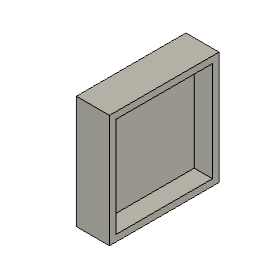
Ensamble_1 (Autodesk Fusion 360 archive; units mm, degrees)
design "caja_pantalla"
Autodesk Fusion 360 part; units mm, degrees
(part 1 of 2)
sketch "Boceto2" plane through (0, 0, 0) normal (1, 0, 0) x (0, 0, -1)
  line L0 (16.5, 17) -> (-16.5, 17)
  line L1 (-16.5, 17) -> (-16.5, -17)
  line L2 (-16.5, -17) -> (16.5, -17)
  line L3 (16.5, -17) -> (16.5, 17)
  line L4 (16.5, 17) -> (-16.5, -17) construction
  line L5 (-16.5, 17) -> (16.5, -17) construction
  dimension "d1" = 33
  dimension "d2" = 34
  constraint horizontal L0
  constraint perpendicular L0 L1
  constraint parallel L0 L2
  constraint parallel L1 L3
  constraint coincident L4 origin
  constraint coincident L5 origin
  measures "d1" distance of L1.end L2.end
  measures "d2" distance of L0.end L1.end
extrude "Extruir1" add sketch "Boceto2" along normal blind 10
sketch "Boceto3" plane through (10, 0, 0) normal (1, 0, 0) x (0, 0, -1)
  line L0 (16.5, -17) -> (16.5, 17)
  line L1 (16.5, 17) -> (-16.5, 17)
  line L2 (-16.5, 17) -> (-16.5, -17)
  line L3 (-16.5, -17) -> (16.5, -17)
  line L4 (14.5, 15) -> (-14.5, 15)
  line L5 (-14.5, 15) -> (-14.5, -15)
  line L6 (-14.5, -15) -> (14.5, -15)
  line L7 (14.5, -15) -> (14.5, 15)
  line L8 (14.5, 15) -> (-14.5, -15) construction
  line L9 (-14.5, 15) -> (14.5, -15) construction
  dimension "d5" = 29
  dimension "d6" = 30
  constraint horizontal L4
  constraint perpendicular L4 L5
  constraint parallel L4 L6
  constraint parallel L5 L7
  constraint coincident L8 origin
  constraint coincident L9 origin
  measures "d5" distance of L5.end L6.end
  measures "d6" distance of L4.end L5.end
extrude "Extruir2" cut sketch "Boceto3" against normal blind 5.5 contours L4 L5 L6 L7
sketch "Boceto4" plane through (4.5, 0, 0) normal (1, 0, 0) x (0, 0, -1)
  line L0 (14.5, -15) -> (14.5, 15)
  line L1 (14.5, 15) -> (-14.5, 15)
  line L2 (-14.5, 15) -> (-14.5, -15)
  line L3 (-14.5, -15) -> (14.5, -15)
  line L4 (5.1, 13.25) -> (-4.9, 13.25)
  line L5 (-4.9, 13.25) -> (-4.9, 10.75)
  line L6 (-4.9, 10.75) -> (5.1, 10.75)
  line L7 (5.1, 10.75) -> (5.1, 13.25)
  line L8 (5.1, 13.25) -> (-4.9, 10.75) construction
  line L9 (-4.9, 13.25) -> (5.1, 10.75) construction
  line L10 (16.5, 17) -> (-16.5, 17)
  point P0 (0.1, 12)
  dimension "d9" = 10
  dimension "d10" = 2.5
  dimension "d11" = 5
  dimension "d26" = 0.1
  constraint horizontal L4
  constraint perpendicular L4 L5
  constraint parallel L4 L6
  constraint parallel L5 L7
  constraint coincident L8 P0
  constraint coincident L9 P0
  measures "d9" distance of L5.end L6.end
  measures "d10" distance of L4.end L5.end
  measures "d11" distance of P0 L10
  measures "d26" horizontal distance of origin P0
extrude "Extruir3" cut sketch "Boceto4" against normal blind 5 contours L4 L5 L6 L7
sketch "Boceto5" plane through (0, 0, 16.5) normal (0, 0, 1) x (1, 0, 0)
  line L0 (0, 17) -> (0, -17)
  line L1 (0, -17) -> (10, -17)
  line L2 (10, -17) -> (10, 17)
  line L3 (10, 17) -> (0, 17)
  line L4 (0, 9.3366) -> (-3.6138, -2.125)
  line L5 (0, -17) -> (-11.8505, -17)
  line L6 (-11.8505, -17) -> (-11.8505, -2.125)
  line L7 (-11.8505, -2.125) -> (-3.6138, -2.125)
  dimension "d14" = 17.5
  constraint coincident L0 L4.start
  constraint coincident L0.end L1.start
  constraint perpendicular L0 L5
  constraint perpendicular L5 L6
  constraint perpendicular L6 L7
  measures "d14" angle of L0 L4
extrude "Extruir4" add sketch "Boceto5" against normal blind 31 contours L0 L4 L5 L6 L7
sketch "Boceto6" plane through (0, 0, 16.5) normal (0, 0, 1) x (1, 0, 0)
  line L0 (0, 17) -> (0, 9.3366)
  line L1 (0, 9.3366) -> (-3.6138, -2.125)
  line L2 (-3.6138, -2.125) -> (-11.8505, -2.125)
  line L3 (-11.8505, -2.125) -> (-11.8505, -17)
  line L4 (-11.8505, -17) -> (10, -17)
  line L5 (10, -17) -> (10, 17)
  line L6 (10, 17) -> (0, 17)
  line L7 (0, 9.3366) -> (-3.6138, -2.125)
  line L8 (-11.8505, -2.125) -> (-11.8505, -17)
  line L9 (0, -17) -> (-11.8505, -17)
  line L10 (-11.8505, -2.125) -> (-11.8505, -17)
  line L11 (0, -17) -> (0, 9.3366)
  line L12 (-11.8505, -2.125) -> (-3.6138, -2.125)
  constraint coincident L0.end L1.start
  constraint coincident L1.end L2.start
  constraint coincident L2.end L3.start
  constraint coincident L3.end L4.start
  constraint coincident L4 L9.start
  constraint perpendicular L9 L11
extrude "Extruir5" cut sketch "Boceto6" against normal blind 20 contours L1 L2 L3 L4 L7 L8 L9 L10 L11 L12
fillet "Empalme1" radius 4 1 edges at (0, -3.8317, -3.5)
sketch "Boceto7" plane through (0, 0, -3.5) normal (0, 0, 1) x (1, 0, 0)
  line L0 (-4, -17) -> (-4, -2.125)
  line L1 (-4, -2.125) -> (-11.8505, -2.125)
  line L2 (-11.8505, -2.125) -> (-11.8505, -17)
  line L3 (-11.8505, -17) -> (-4, -17)
  circle A0 centre (-7.9252, -9.0625) radius 1.95
  dimension "d21" = 3.9
  measures "d21" diameter of A0
extrude "Extruir6" cut sketch "Boceto7" against normal blind 15 contours A0
fillet "Empalme2" radius 1 1 edges at (-9.7433, -8.3574, -3.5)

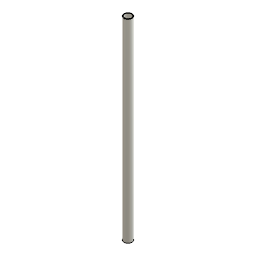
design "eslabon_pendulo_30cm"
Autodesk Fusion 360 part; units mm, degrees
sketch "Boceto1" plane through (0, 0, 0) normal (0, 1, 0) x (1, 0, 0)
  circle A0 centre (0, 0) radius 6.35
  circle A1 centre (0, 0) radius 5.35
  dimension "d1" = 12.7
  dimension "d2" = 10.7
  constraint coincident A0.centre A1.centre
  measures "d1" diameter of A0
  measures "d2" diameter of A1
extrude "Extruir1" add sketch "Boceto1" along normal blind 300

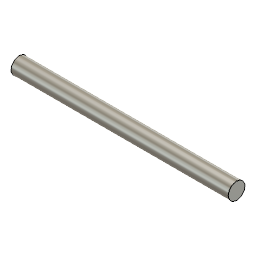
design "Eje_pendulo"
Autodesk Fusion 360 part; units mm, degrees
sketch "Boceto1" plane through (0, 0, 0) normal (1, 0, 0) x (0, 0, -1)
  circle A0 centre (0, 0) radius 5
  dimension "d1" = 10
  constraint coincident A0.centre origin
  measures "d1" diameter of A0
extrude "Extruir1" add sketch "Boceto1" along normal blind 130

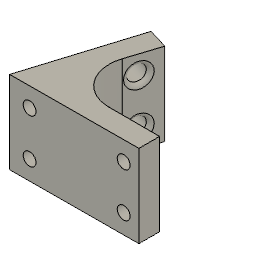
design "soporte_final_de_carrera_izquierdo"
Autodesk Fusion 360 part; units mm, degrees
sketch "Boceto1" plane through (0, 0, 0) normal (0, 1, 0) x (1, 0, 0)
sketch "Boceto2" plane through (0, 0, 0) normal (0, 1, 0) x (1, 0, 0)
  line L0 (-2.4765, -16.3875) -> (28.7043, -16.2321)
  line L1 (-0.8695, -11.2008) -> (-2.4765, -16.3875)
  line L2 (28.7038, -11.2321) -> (-0.8695, -11.2008)
  line L3 (28.7043, -16.2321) -> (28.7038, -11.2321)
  line L4 (0.003, -0.5995) -> (0.0504, -0.0236)
  line L5 (5.8748, 9.7875) -> (5.6392, 9.8069)
  line L6 (-2.0966, -0.0236) -> (7.9894, -0.0236) construction
  line L7 (-0.8695, -11.2008) -> (0.0412, -8.2614)
  line L8 (0.0412, -8.2614) -> (3.4344, 2.6907)
  line L9 (3.4344, 2.6907) -> (5.6392, 9.8069)
  line L10 (5.6392, 9.8069) -> (10.4153, 8.3271)
  line L11 (10.4153, 8.3271) -> (4.1469, -11.2061)
  line L12 (5.8705, 9.7352) -> (5.8748, 9.7875)
  line L13 (0, 0) -> (0.003, -0.5995) construction
  line L14 (0.0412, -8.2614) -> (0.0922, -18.4956) construction
  point P0 (3.4743, -16.237)
  point P1 (-1.1967, -15.176)
  point P2 (-1.5762, -19.7876)
  dimension "d1" = 5
  dimension "d3" = 5.1866
  dimension "d4" = 17.5
  dimension "d27" = 3.0772
  dimension "d28" = 5
  constraint coincident L11.end L2
  constraint coincident L13.start origin
  constraint perpendicular L0 L14
  constraint perpendicular L4 L5
  constraint parallel L1 L7
  constraint parallel L7 L8
  constraint parallel L8 L9
  constraint perpendicular L9 L10
  constraint coincident L10 L12.start
  constraint collinear L13 L14
  measures "d1" distance of L2.start L0.end
  measures "d3" vertical distance of L1.start L0.start
  measures "d4" angle of L1 L14
  measures "d27" distance of L1.start L7.end
  measures "d28" distance of L5.end L10.end
extrude "Extruir1" add sketch "Boceto2" along normal blind 20 contours L0 L1 L2 L3 | L2 L7 L8 L9 L10 L11
sketch "Boceto4" plane through (0.0816, 0, 16.3747) normal (0.004984, 0, 0.999988) x (0.999988, 0, -0.004984)
  line L0 (-2.5581, 0) -> (28.6231, 0)
  line L1 (28.6231, 0) -> (28.6231, 20)
  line L2 (28.6231, 20) -> (-2.5581, 20)
  line L3 (-2.5581, 20) -> (-2.5581, 0)
  line L4 (-0.378, 2.01) -> (27.622, 2.01)
  line L5 (27.622, 2.01) -> (27.622, 18.01)
  line L6 (27.622, 18.01) -> (-0.378, 18.01)
  line L7 (-0.378, 18.01) -> (-0.378, 2.01)
  line L8 (-0.378, 2.01) -> (27.622, 18.01) construction
  line L9 (27.622, 2.01) -> (-0.378, 18.01) construction
  circle A0 centre (2.292, 15.34) radius 1.55
  line L10 (13.622, 8.2976) -> (13.622, 12.2565) construction
  line L11 (11.7827, 10.01) -> (15.7906, 10.01) construction
  circle A1 centre (24.952, 15.34) radius 1.55
  circle A2 centre (24.952, 4.68) radius 1.55
  circle A3 centre (2.292, 4.68) radius 1.55
  point P0 (13.622, 10.01)
  dimension "d17" = 28
  dimension "d18" = 16
  dimension "d19" = 3.1
  dimension "d20" = 2.67
  dimension "d21" = 2.67
  constraint horizontal L4
  constraint perpendicular L4 L5
  constraint parallel L4 L6
  constraint parallel L5 L7
  constraint coincident L8 P0
  constraint coincident L9 P0
  constraint perpendicular L2 L10
  constraint perpendicular L10 L11
  constraint symmetric A0 L10 A1
  constraint symmetric A0 L11 A3
  constraint symmetric L11 A1 A2
  measures "d17" distance of L5.end L6.end
  measures "d18" distance of L4.end L5.end
  measures "d19" diameter of A0
  measures "d20" distance of L6 A0.centre
  measures "d21" distance of L7 A0.centre
extrude "Extruir3" cut sketch "Boceto4" against normal blind 6 contours A0 | A1 | A2 | A3
sketch "Boceto5" plane through (7.0201, 0, 2.2528) normal (0.952174, 0, 0.305557) x (0.305557, 0, -0.952174)
  line L0 (-9.4031, 0) -> (11.1113, 0)
  line L1 (11.1113, 0) -> (11.1113, 20)
  line L2 (11.1113, 20) -> (-9.4031, 20)
  line L3 (-9.4031, 20) -> (-9.4031, 0)
  circle A0 centre (6.1113, 4.5) radius 1.95
  circle A1 centre (6.1113, 15.5) radius 1.95
  dimension "d29" = 3.9
  dimension "d30" = 4.5
  dimension "d31" = 3.9
  dimension "d32" = 4.5
  dimension "d33" = 5
  dimension "d34" = 5
  measures "d29" diameter of A0
  measures "d30" distance of L0 A0.centre
  measures "d31" diameter of A1
  measures "d32" distance of L2 A1.centre
  measures "d33" distance of L1 A0.centre
  measures "d34" distance of L1 A1.centre
extrude "Extruir4" cut sketch "Boceto5" against normal blind 7 contours A0 | A1
fillet "Empalme3" radius 1 2 edges at (8.332, 5.2052, -1.8352) (8.332, 16.2052, -1.8352)
fillet "Empalme4" radius 9 1 edges at (4.1469, 10, 11.2061)
equation "d20 = 1.12 mm + ( 3.1 / 2 ) * 1 mm"
equation "d21 = 1.12 mm + ( 3.1 / 2 ) * 1 mm"

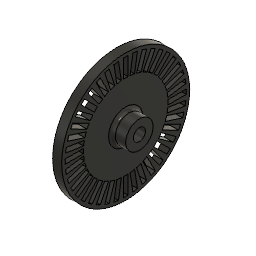
design "rueda_dentada_encoder"
Autodesk Fusion 360 part; units mm, degrees
sketch "Boceto1" plane through (0, 0, 0) normal (1, 0, 0) x (0, 0, -1)
  circle A0 centre (0, 0) radius 28
  line L0 (1.644, -2.0784) -> (1.644, 2.0784)
  line L1 (1.644, 2.0784) -> (-1.5819, -2) construction
  line L2 (-1.5819, 2) -> (1.644, -2.0784) construction
  arc A1 (1.644, 2.0784) -> (1.644, -2.0784) centre (0, 0) ccw
  circle A2 centre (0, 0) radius 26.5 construction
  line L3 (0, 0) -> (0, 29.9293) construction
  line L4 (0, 26.5) -> (-4.3464, 26.5) construction
  line L5 (0, 26.5) -> (0, 18.5)
  line L6 (0, 18.5) -> (-1, 18.5)
  line L7 (-1, 18.5) -> (-1, 26.5)
  line L8 (-1, 26.5) -> (0, 26.5)
  line L9 (1, 26.5) -> (0, 26.5)
  line L10 (1, 18.5) -> (1, 26.5)
  line L11 (0, 18.5) -> (1, 18.5)
  line L12 (-3.8817, 18.1158) -> (-5.1332, 26.0173)
  line L13 (-5.1332, 26.0173) -> (-4.1455, 26.1737)
  line L14 (-3.1578, 26.3302) -> (-4.1455, 26.1737)
  line L15 (-1.9063, 18.4287) -> (-3.1578, 26.3302)
  line L16 (-2.894, 18.2722) -> (-1.9063, 18.4287)
  line L17 (-2.894, 18.2722) -> (-3.8817, 18.1158)
  line L18 (-6.6679, 17.2855) -> (-9.14, 24.894)
  line L19 (-9.14, 24.894) -> (-8.189, 25.203)
  line L20 (-7.2379, 25.512) -> (-8.189, 25.203)
  line L21 (-4.7658, 17.9036) -> (-7.2379, 25.512)
  line L22 (-5.7168, 17.5945) -> (-4.7658, 17.9036)
  line L23 (-5.7168, 17.5945) -> (-6.6679, 17.2855)
  line L24 (-9.2898, 16.0296) -> (-12.9218, 23.1577)
  line L25 (-12.9218, 23.1577) -> (-12.0307, 23.6117)
  line L26 (-11.1397, 24.0657) -> (-12.0307, 23.6117)
  line L27 (-7.5078, 16.9376) -> (-11.1397, 24.0657)
  line L28 (-8.3988, 16.4836) -> (-7.5078, 16.9376)
  line L29 (-8.3988, 16.4836) -> (-9.2898, 16.0296)
  line L30 (-11.683, 14.379) -> (-16.3853, 20.8512)
  line L31 (-16.3853, 20.8512) -> (-15.5763, 21.439)
  line L32 (-14.7673, 22.0267) -> (-15.5763, 21.439)
  line L33 (-10.065, 15.5546) -> (-14.7673, 22.0267)
  line L34 (-10.874, 14.9668) -> (-10.065, 15.5546)
  line L35 (-10.874, 14.9668) -> (-11.683, 14.379)
  line L36 (-13.7886, 12.3744) -> (-19.4454, 18.0312)
  line L37 (-19.4454, 18.0312) -> (-18.7383, 18.7383)
  line L38 (-18.0312, 19.4454) -> (-18.7383, 18.7383)
  line L39 (-12.3744, 13.7886) -> (-18.0312, 19.4454)
  line L40 (-13.0815, 13.0815) -> (-12.3744, 13.7886)
  line L41 (-13.0815, 13.0815) -> (-13.7886, 12.3744)
  line L42 (-15.5546, 10.065) -> (-22.0267, 14.7673)
  line L43 (-22.0267, 14.7673) -> (-21.439, 15.5763)
  line L44 (-20.8512, 16.3853) -> (-21.439, 15.5763)
  line L45 (-14.379, 11.683) -> (-20.8512, 16.3853)
  line L46 (-14.9668, 10.874) -> (-14.379, 11.683)
  line L47 (-14.9668, 10.874) -> (-15.5546, 10.065)
  line L48 (-16.9376, 7.5078) -> (-24.0657, 11.1397)
  line L49 (-24.0657, 11.1397) -> (-23.6117, 12.0307)
  line L50 (-23.1577, 12.9218) -> (-23.6117, 12.0307)
  line L51 (-16.0296, 9.2898) -> (-23.1577, 12.9218)
  line L52 (-16.4836, 8.3988) -> (-16.0296, 9.2898)
  line L53 (-16.4836, 8.3988) -> (-16.9376, 7.5078)
  line L54 (-17.9036, 4.7658) -> (-25.512, 7.2379)
  line L55 (-25.512, 7.2379) -> (-25.203, 8.189)
  line L56 (-24.894, 9.14) -> (-25.203, 8.189)
  line L57 (-17.2855, 6.6679) -> (-24.894, 9.14)
  line L58 (-17.5945, 5.7168) -> (-17.2855, 6.6679)
  line L59 (-17.5945, 5.7168) -> (-17.9036, 4.7658)
  line L60 (-18.4287, 1.9063) -> (-26.3302, 3.1578)
  line L61 (-26.3302, 3.1578) -> (-26.1737, 4.1455)
  line L62 (-26.0173, 5.1332) -> (-26.1737, 4.1455)
  line L63 (-18.1158, 3.8817) -> (-26.0173, 5.1332)
  line L64 (-18.2722, 2.894) -> (-18.1158, 3.8817)
  line L65 (-18.2722, 2.894) -> (-18.4287, 1.9063)
  line L66 (-18.5, -1) -> (-26.5, -1)
  line L67 (-26.5, -1) -> (-26.5, 0)
  line L68 (-26.5, 1) -> (-26.5, 0)
  line L69 (-18.5, 1) -> (-26.5, 1)
  line L70 (-18.5, 0) -> (-18.5, 1)
  line L71 (-18.5, 0) -> (-18.5, -1)
  line L72 (-18.1158, -3.8817) -> (-26.0173, -5.1332)
  line L73 (-26.0173, -5.1332) -> (-26.1737, -4.1455)
  line L74 (-26.3302, -3.1578) -> (-26.1737, -4.1455)
  line L75 (-18.4287, -1.9063) -> (-26.3302, -3.1578)
  line L76 (-18.2722, -2.894) -> (-18.4287, -1.9063)
  line L77 (-18.2722, -2.894) -> (-18.1158, -3.8817)
  line L78 (-17.2855, -6.6679) -> (-24.894, -9.14)
  line L79 (-24.894, -9.14) -> (-25.203, -8.189)
  line L80 (-25.512, -7.2379) -> (-25.203, -8.189)
  line L81 (-17.9036, -4.7658) -> (-25.512, -7.2379)
  line L82 (-17.5945, -5.7168) -> (-17.9036, -4.7658)
  line L83 (-17.5945, -5.7168) -> (-17.2855, -6.6679)
  line L84 (-16.0296, -9.2898) -> (-23.1577, -12.9218)
  line L85 (-23.1577, -12.9218) -> (-23.6117, -12.0307)
  line L86 (-24.0657, -11.1397) -> (-23.6117, -12.0307)
  line L87 (-16.9376, -7.5078) -> (-24.0657, -11.1397)
  line L88 (-16.4836, -8.3988) -> (-16.9376, -7.5078)
  line L89 (-16.4836, -8.3988) -> (-16.0296, -9.2898)
  line L90 (-14.379, -11.683) -> (-20.8512, -16.3853)
  line L91 (-20.8512, -16.3853) -> (-21.439, -15.5763)
  line L92 (-22.0267, -14.7673) -> (-21.439, -15.5763)
  line L93 (-15.5546, -10.065) -> (-22.0267, -14.7673)
  line L94 (-14.9668, -10.874) -> (-15.5546, -10.065)
  line L95 (-14.9668, -10.874) -> (-14.379, -11.683)
  line L96 (-12.3744, -13.7886) -> (-18.0312, -19.4454)
  line L97 (-18.0312, -19.4454) -> (-18.7383, -18.7383)
  line L98 (-19.4454, -18.0312) -> (-18.7383, -18.7383)
  line L99 (-13.7886, -12.3744) -> (-19.4454, -18.0312)
  line L100 (-13.0815, -13.0815) -> (-13.7886, -12.3744)
  line L101 (-13.0815, -13.0815) -> (-12.3744, -13.7886)
  line L102 (-10.065, -15.5546) -> (-14.7673, -22.0267)
  line L103 (-14.7673, -22.0267) -> (-15.5763, -21.439)
  line L104 (-16.3853, -20.8512) -> (-15.5763, -21.439)
  line L105 (-11.683, -14.379) -> (-16.3853, -20.8512)
  line L106 (-10.874, -14.9668) -> (-11.683, -14.379)
  line L107 (-10.874, -14.9668) -> (-10.065, -15.5546)
  line L108 (-7.5078, -16.9376) -> (-11.1397, -24.0657)
  line L109 (-11.1397, -24.0657) -> (-12.0307, -23.6117)
  line L110 (-12.9218, -23.1577) -> (-12.0307, -23.6117)
  line L111 (-9.2898, -16.0296) -> (-12.9218, -23.1577)
  line L112 (-8.3988, -16.4836) -> (-9.2898, -16.0296)
  line L113 (-8.3988, -16.4836) -> (-7.5078, -16.9376)
  line L114 (-4.7658, -17.9036) -> (-7.2379, -25.512)
  line L115 (-7.2379, -25.512) -> (-8.189, -25.203)
  line L116 (-9.14, -24.894) -> (-8.189, -25.203)
  line L117 (-6.6679, -17.2855) -> (-9.14, -24.894)
  line L118 (-5.7168, -17.5945) -> (-6.6679, -17.2855)
  line L119 (-5.7168, -17.5945) -> (-4.7658, -17.9036)
  line L120 (-1.9063, -18.4287) -> (-3.1578, -26.3302)
  line L121 (-3.1578, -26.3302) -> (-4.1455, -26.1737)
  line L122 (-5.1332, -26.0173) -> (-4.1455, -26.1737)
  line L123 (-3.8817, -18.1158) -> (-5.1332, -26.0173)
  line L124 (-2.894, -18.2722) -> (-3.8817, -18.1158)
  line L125 (-2.894, -18.2722) -> (-1.9063, -18.4287)
  line L126 (1, -18.5) -> (1, -26.5)
  line L127 (1, -26.5) -> (0, -26.5)
  line L128 (-1, -26.5) -> (0, -26.5)
  line L129 (-1, -18.5) -> (-1, -26.5)
  line L130 (0, -18.5) -> (-1, -18.5)
  line L131 (0, -18.5) -> (1, -18.5)
  line L132 (3.8817, -18.1158) -> (5.1332, -26.0173)
  line L133 (5.1332, -26.0173) -> (4.1455, -26.1737)
  line L134 (3.1578, -26.3302) -> (4.1455, -26.1737)
  line L135 (1.9063, -18.4287) -> (3.1578, -26.3302)
  line L136 (2.894, -18.2722) -> (1.9063, -18.4287)
  line L137 (2.894, -18.2722) -> (3.8817, -18.1158)
  line L138 (6.6679, -17.2855) -> (9.14, -24.894)
  line L139 (9.14, -24.894) -> (8.189, -25.203)
  line L140 (7.2379, -25.512) -> (8.189, -25.203)
  line L141 (4.7658, -17.9036) -> (7.2379, -25.512)
  line L142 (5.7168, -17.5945) -> (4.7658, -17.9036)
  line L143 (5.7168, -17.5945) -> (6.6679, -17.2855)
  line L144 (9.2898, -16.0296) -> (12.9218, -23.1577)
  line L145 (12.9218, -23.1577) -> (12.0307, -23.6117)
  line L146 (11.1397, -24.0657) -> (12.0307, -23.6117)
  line L147 (7.5078, -16.9376) -> (11.1397, -24.0657)
  line L148 (8.3988, -16.4836) -> (7.5078, -16.9376)
  line L149 (8.3988, -16.4836) -> (9.2898, -16.0296)
  line L150 (11.683, -14.379) -> (16.3853, -20.8512)
  line L151 (16.3853, -20.8512) -> (15.5763, -21.439)
  line L152 (14.7673, -22.0267) -> (15.5763, -21.439)
  line L153 (10.065, -15.5546) -> (14.7673, -22.0267)
  line L154 (10.874, -14.9668) -> (10.065, -15.5546)
  line L155 (10.874, -14.9668) -> (11.683, -14.379)
  line L156 (13.7886, -12.3744) -> (19.4454, -18.0312)
  line L157 (19.4454, -18.0312) -> (18.7383, -18.7383)
  line L158 (18.0312, -19.4454) -> (18.7383, -18.7383)
  line L159 (12.3744, -13.7886) -> (18.0312, -19.4454)
  line L160 (13.0815, -13.0815) -> (12.3744, -13.7886)
  line L161 (13.0815, -13.0815) -> (13.7886, -12.3744)
  line L162 (15.5546, -10.065) -> (22.0267, -14.7673)
  line L163 (22.0267, -14.7673) -> (21.439, -15.5763)
  line L164 (20.8512, -16.3853) -> (21.439, -15.5763)
  line L165 (14.379, -11.683) -> (20.8512, -16.3853)
  line L166 (14.9668, -10.874) -> (14.379, -11.683)
  line L167 (14.9668, -10.874) -> (15.5546, -10.065)
  line L168 (16.9376, -7.5078) -> (24.0657, -11.1397)
  line L169 (24.0657, -11.1397) -> (23.6117, -12.0307)
  line L170 (23.1577, -12.9218) -> (23.6117, -12.0307)
  line L171 (16.0296, -9.2898) -> (23.1577, -12.9218)
  line L172 (16.4836, -8.3988) -> (16.0296, -9.2898)
  line L173 (16.4836, -8.3988) -> (16.9376, -7.5078)
  line L174 (17.9036, -4.7658) -> (25.512, -7.2379)
  line L175 (25.512, -7.2379) -> (25.203, -8.189)
  line L176 (24.894, -9.14) -> (25.203, -8.189)
  line L177 (17.2855, -6.6679) -> (24.894, -9.14)
  line L178 (17.5945, -5.7168) -> (17.2855, -6.6679)
  line L179 (17.5945, -5.7168) -> (17.9036, -4.7658)
  line L180 (18.4287, -1.9063) -> (26.3302, -3.1578)
  line L181 (26.3302, -3.1578) -> (26.1737, -4.1455)
  line L182 (26.0173, -5.1332) -> (26.1737, -4.1455)
  line L183 (18.1158, -3.8817) -> (26.0173, -5.1332)
  line L184 (18.2722, -2.894) -> (18.1158, -3.8817)
  line L185 (18.2722, -2.894) -> (18.4287, -1.9063)
  line L186 (18.5, 1) -> (26.5, 1)
  line L187 (26.5, 1) -> (26.5, 0)
  line L188 (26.5, -1) -> (26.5, 0)
  line L189 (18.5, -1) -> (26.5, -1)
  line L190 (18.5, 0) -> (18.5, -1)
  line L191 (18.5, 0) -> (18.5, 1)
  line L192 (18.1158, 3.8817) -> (26.0173, 5.1332)
  line L193 (26.0173, 5.1332) -> (26.1737, 4.1455)
  line L194 (26.3302, 3.1578) -> (26.1737, 4.1455)
  line L195 (18.4287, 1.9063) -> (26.3302, 3.1578)
  line L196 (18.2722, 2.894) -> (18.4287, 1.9063)
  line L197 (18.2722, 2.894) -> (18.1158, 3.8817)
  line L198 (17.2855, 6.6679) -> (24.894, 9.14)
  line L199 (24.894, 9.14) -> (25.203, 8.189)
  line L200 (25.512, 7.2379) -> (25.203, 8.189)
  line L201 (17.9036, 4.7658) -> (25.512, 7.2379)
  line L202 (17.5945, 5.7168) -> (17.9036, 4.7658)
  line L203 (17.5945, 5.7168) -> (17.2855, 6.6679)
  line L204 (16.0296, 9.2898) -> (23.1577, 12.9218)
  line L205 (23.1577, 12.9218) -> (23.6117, 12.0307)
  line L206 (24.0657, 11.1397) -> (23.6117, 12.0307)
  line L207 (16.9376, 7.5078) -> (24.0657, 11.1397)
  line L208 (16.4836, 8.3988) -> (16.9376, 7.5078)
  line L209 (16.4836, 8.3988) -> (16.0296, 9.2898)
  line L210 (14.379, 11.683) -> (20.8512, 16.3853)
  line L211 (20.8512, 16.3853) -> (21.439, 15.5763)
  line L212 (22.0267, 14.7673) -> (21.439, 15.5763)
  line L213 (15.5546, 10.065) -> (22.0267, 14.7673)
  line L214 (14.9668, 10.874) -> (15.5546, 10.065)
  line L215 (14.9668, 10.874) -> (14.379, 11.683)
  line L216 (12.3744, 13.7886) -> (18.0312, 19.4454)
  line L217 (18.0312, 19.4454) -> (18.7383, 18.7383)
  line L218 (19.4454, 18.0312) -> (18.7383, 18.7383)
  line L219 (13.7886, 12.3744) -> (19.4454, 18.0312)
  line L220 (13.0815, 13.0815) -> (13.7886, 12.3744)
  line L221 (13.0815, 13.0815) -> (12.3744, 13.7886)
  line L222 (10.065, 15.5546) -> (14.7673, 22.0267)
  line L223 (14.7673, 22.0267) -> (15.5763, 21.439)
  line L224 (16.3853, 20.8512) -> (15.5763, 21.439)
  line L225 (11.683, 14.379) -> (16.3853, 20.8512)
  line L226 (10.874, 14.9668) -> (11.683, 14.379)
  line L227 (10.874, 14.9668) -> (10.065, 15.5546)
  line L228 (7.5078, 16.9376) -> (11.1397, 24.0657)
  line L229 (11.1397, 24.0657) -> (12.0307, 23.6117)
  line L230 (12.9218, 23.1577) -> (12.0307, 23.6117)
  line L231 (9.2898, 16.0296) -> (12.9218, 23.1577)
  line L232 (8.3988, 16.4836) -> (9.2898, 16.0296)
  line L233 (8.3988, 16.4836) -> (7.5078, 16.9376)
  line L234 (4.7658, 17.9036) -> (7.2379, 25.512)
  line L235 (7.2379, 25.512) -> (8.189, 25.203)
  line L236 (9.14, 24.894) -> (8.189, 25.203)
  line L237 (6.6679, 17.2855) -> (9.14, 24.894)
  line L238 (5.7168, 17.5945) -> (6.6679, 17.2855)
  line L239 (5.7168, 17.5945) -> (4.7658, 17.9036)
  line L240 (1.9063, 18.4287) -> (3.1578, 26.3302)
  line L241 (3.1578, 26.3302) -> (4.1455, 26.1737)
  line L242 (5.1332, 26.0173) -> (4.1455, 26.1737)
  line L243 (3.8817, 18.1158) -> (5.1332, 26.0173)
  line L244 (2.894, 18.2722) -> (3.8817, 18.1158)
  line L245 (2.894, 18.2722) -> (1.9063, 18.4287)
  dimension "d1" = 56
  dimension "d2" = 5.3
  dimension "d3" = 4
  dimension "d4" = 53
  dimension "d5" = 8
  dimension "d6" = 1
  dimension "d8" = 360
  constraint coincident A0.centre A1.centre
  constraint coincident L1 A0.centre
  constraint coincident L2 A0.centre
  constraint concentric A1 A2
  constraint vertical L3
  constraint coincident A2 L4.start
  constraint coincident L3 L4.start
  constraint tangent A2 L4
  constraint perpendicular L5 L6
  constraint parallel L5 L7
  constraint parallel L6 L8
  constraint coincident L3 L5.end
  constraint symmetric L3 L4.start L5.start
  constraint symmetric L3 L5.end L6.start
  constraint symmetric L3 L6.end L10.start
  constraint symmetric L3 L7.end L9.start
  measures "d1" diameter of A0
  measures "d2" diameter of A1
  measures "d3" distance of L2.start L1.end
  measures "d4" diameter of A2
  measures "d5" distance of L4.start L5.end
  measures "d6" distance of L4.start L7.end
extrude "Extruir1" add sketch "Boceto1" along normal blind 4
sketch "Boceto2" plane through (4, 0, 0) normal (1, 0, 0) x (0, 0, -1)
  line L0 (5.1332, 26.0173) -> (3.8817, 18.1158)
  line L1 (3.8817, 18.1158) -> (1.9063, 18.4287)
  line L2 (1.9063, 18.4287) -> (3.1578, 26.3302)
  line L3 (3.1578, 26.3302) -> (5.1332, 26.0173)
  line L4 (19.4454, 18.0312) -> (13.7886, 12.3744)
  line L5 (13.7886, 12.3744) -> (12.3744, 13.7886)
  line L6 (12.3744, 13.7886) -> (18.0312, 19.4454)
  line L7 (18.0312, 19.4454) -> (19.4454, 18.0312)
  line L8 (12.9218, 23.1577) -> (9.2898, 16.0296)
  line L9 (9.2898, 16.0296) -> (7.5078, 16.9376)
  line L10 (7.5078, 16.9376) -> (11.1397, 24.0657)
  line L11 (11.1397, 24.0657) -> (12.9218, 23.1577)
  line L12 (-25.512, -7.2379) -> (-17.9036, -4.7658)
  line L13 (-17.9036, -4.7658) -> (-17.2855, -6.6679)
  line L14 (-17.2855, -6.6679) -> (-24.894, -9.14)
  line L15 (-24.894, -9.14) -> (-25.512, -7.2379)
  line L16 (-26.5, 1) -> (-18.5, 1)
  line L17 (-18.5, 1) -> (-18.5, -1)
  line L18 (-18.5, -1) -> (-26.5, -1)
  line L19 (-26.5, -1) -> (-26.5, 1)
  line L20 (-26.0173, 5.1332) -> (-18.1158, 3.8817)
  line L21 (-18.1158, 3.8817) -> (-18.4287, 1.9063)
  line L22 (-18.4287, 1.9063) -> (-26.3302, 3.1578)
  line L23 (-26.3302, 3.1578) -> (-26.0173, 5.1332)
  line L24 (16.3853, 20.8512) -> (11.683, 14.379)
  line L25 (11.683, 14.379) -> (10.065, 15.5546)
  line L26 (10.065, 15.5546) -> (14.7673, 22.0267)
  line L27 (14.7673, 22.0267) -> (16.3853, 20.8512)
  line L28 (-24.894, 9.14) -> (-17.2855, 6.6679)
  line L29 (-17.2855, 6.6679) -> (-17.9036, 4.7658)
  line L30 (-17.9036, 4.7658) -> (-25.512, 7.2379)
  line L31 (-25.512, 7.2379) -> (-24.894, 9.14)
  line L32 (-20.8512, 16.3853) -> (-14.379, 11.683)
  line L33 (-14.379, 11.683) -> (-15.5546, 10.065)
  line L34 (-15.5546, 10.065) -> (-22.0267, 14.7673)
  line L35 (-22.0267, 14.7673) -> (-20.8512, 16.3853)
  line L36 (-18.0312, 19.4454) -> (-12.3744, 13.7886)
  line L37 (-12.3744, 13.7886) -> (-13.7886, 12.3744)
  line L38 (-13.7886, 12.3744) -> (-19.4454, 18.0312)
  line L39 (-19.4454, 18.0312) -> (-18.0312, 19.4454)
  arc A0 (1.644, 2.0784) -> (1.644, -2.0784) centre (0, 0) ccw
  line L40 (1.644, 2.0784) -> (1.644, -2.0784)
  line L41 (-3.1578, 26.3302) -> (-1.9063, 18.4287)
  line L42 (-1.9063, 18.4287) -> (-3.8817, 18.1158)
  line L43 (-3.8817, 18.1158) -> (-5.1332, 26.0173)
  line L44 (-5.1332, 26.0173) -> (-3.1578, 26.3302)
  line L45 (-7.2379, 25.512) -> (-4.7658, 17.9036)
  line L46 (-4.7658, 17.9036) -> (-6.6679, 17.2855)
  line L47 (-6.6679, 17.2855) -> (-9.14, 24.894)
  line L48 (-9.14, 24.894) -> (-7.2379, 25.512)
  line L49 (-11.1397, 24.0657) -> (-7.5078, 16.9376)
  line L50 (-7.5078, 16.9376) -> (-9.2898, 16.0296)
  line L51 (-9.2898, 16.0296) -> (-12.9218, 23.1577)
  line L52 (-12.9218, 23.1577) -> (-11.1397, 24.0657)
  line L53 (-14.7673, 22.0267) -> (-10.065, 15.5546)
  line L54 (-10.065, 15.5546) -> (-11.683, 14.379)
  line L55 (-11.683, 14.379) -> (-16.3853, 20.8512)
  line L56 (-16.3853, 20.8512) -> (-14.7673, 22.0267)
  line L57 (-12.9218, -23.1577) -> (-9.2898, -16.0296)
  line L58 (-9.2898, -16.0296) -> (-7.5078, -16.9376)
  line L59 (-7.5078, -16.9376) -> (-11.1397, -24.0657)
  line L60 (-11.1397, -24.0657) -> (-12.9218, -23.1577)
  line L61 (-5.1332, -26.0173) -> (-3.8817, -18.1158)
  line L62 (-3.8817, -18.1158) -> (-1.9063, -18.4287)
  line L63 (-1.9063, -18.4287) -> (-3.1578, -26.3302)
  line L64 (-3.1578, -26.3302) -> (-5.1332, -26.0173)
  line L65 (-19.4454, -18.0312) -> (-13.7886, -12.3744)
  line L66 (-13.7886, -12.3744) -> (-12.3744, -13.7886)
  line L67 (-12.3744, -13.7886) -> (-18.0312, -19.4454)
  line L68 (-18.0312, -19.4454) -> (-19.4454, -18.0312)
  line L69 (9.14, 24.894) -> (6.6679, 17.2855)
  line L70 (6.6679, 17.2855) -> (4.7658, 17.9036)
  line L71 (4.7658, 17.9036) -> (7.2379, 25.512)
  line L72 (7.2379, 25.512) -> (9.14, 24.894)
  line L73 (-9.14, -24.894) -> (-6.6679, -17.2855)
  line L74 (-6.6679, -17.2855) -> (-4.7658, -17.9036)
  line L75 (-4.7658, -17.9036) -> (-7.2379, -25.512)
  line L76 (-7.2379, -25.512) -> (-9.14, -24.894)
  line L77 (20.8512, -16.3853) -> (14.379, -11.683)
  line L78 (14.379, -11.683) -> (15.5546, -10.065)
  line L79 (15.5546, -10.065) -> (22.0267, -14.7673)
  line L80 (22.0267, -14.7673) -> (20.8512, -16.3853)
  line L81 (-24.0657, -11.1397) -> (-16.9376, -7.5078)
  line L82 (-16.9376, -7.5078) -> (-16.0296, -9.2898)
  line L83 (-16.0296, -9.2898) -> (-23.1577, -12.9218)
  line L84 (-23.1577, -12.9218) -> (-24.0657, -11.1397)
  line L85 (23.1577, -12.9218) -> (16.0296, -9.2898)
  line L86 (16.0296, -9.2898) -> (16.9376, -7.5078)
  line L87 (16.9376, -7.5078) -> (24.0657, -11.1397)
  line L88 (24.0657, -11.1397) -> (23.1577, -12.9218)
  line L89 (-1, -26.5) -> (-1, -18.5)
  line L90 (-1, -18.5) -> (1, -18.5)
  line L91 (1, -18.5) -> (1, -26.5)
  line L92 (1, -26.5) -> (-1, -26.5)
  line L93 (14.7673, -22.0267) -> (10.065, -15.5546)
  line L94 (10.065, -15.5546) -> (11.683, -14.379)
  line L95 (11.683, -14.379) -> (16.3853, -20.8512)
  line L96 (16.3853, -20.8512) -> (14.7673, -22.0267)
  line L97 (24.894, -9.14) -> (17.2855, -6.6679)
  line L98 (17.2855, -6.6679) -> (17.9036, -4.7658)
  line L99 (17.9036, -4.7658) -> (25.512, -7.2379)
  line L100 (25.512, -7.2379) -> (24.894, -9.14)
  line L101 (26.0173, -5.1332) -> (18.1158, -3.8817)
  line L102 (18.1158, -3.8817) -> (18.4287, -1.9063)
  line L103 (18.4287, -1.9063) -> (26.3302, -3.1578)
  line L104 (26.3302, -3.1578) -> (26.0173, -5.1332)
  line L105 (-26.3302, -3.1578) -> (-18.4287, -1.9063)
  line L106 (-18.4287, -1.9063) -> (-18.1158, -3.8817)
  line L107 (-18.1158, -3.8817) -> (-26.0173, -5.1332)
  line L108 (-26.0173, -5.1332) -> (-26.3302, -3.1578)
  line L109 (3.1578, -26.3302) -> (1.9063, -18.4287)
  line L110 (1.9063, -18.4287) -> (3.8817, -18.1158)
  line L111 (3.8817, -18.1158) -> (5.1332, -26.0173)
  line L112 (5.1332, -26.0173) -> (3.1578, -26.3302)
  line L113 (-22.0267, -14.7673) -> (-15.5546, -10.065)
  line L114 (-15.5546, -10.065) -> (-14.379, -11.683)
  line L115 (-14.379, -11.683) -> (-20.8512, -16.3853)
  line L116 (-20.8512, -16.3853) -> (-22.0267, -14.7673)
  line L117 (26.5, -1) -> (18.5, -1)
  line L118 (18.5, -1) -> (18.5, 1)
  line L119 (18.5, 1) -> (26.5, 1)
  line L120 (26.5, 1) -> (26.5, -1)
  line L121 (7.2379, -25.512) -> (4.7658, -17.9036)
  line L122 (4.7658, -17.9036) -> (6.6679, -17.2855)
  line L123 (6.6679, -17.2855) -> (9.14, -24.894)
  line L124 (9.14, -24.894) -> (7.2379, -25.512)
  line L125 (11.1397, -24.0657) -> (7.5078, -16.9376)
  line L126 (7.5078, -16.9376) -> (9.2898, -16.0296)
  line L127 (9.2898, -16.0296) -> (12.9218, -23.1577)
  line L128 (12.9218, -23.1577) -> (11.1397, -24.0657)
  line L129 (25.512, 7.2379) -> (17.9036, 4.7658)
  line L130 (17.9036, 4.7658) -> (17.2855, 6.6679)
  line L131 (17.2855, 6.6679) -> (24.894, 9.14)
  line L132 (24.894, 9.14) -> (25.512, 7.2379)
  line L133 (1, 18.5) -> (-1, 18.5)
  line L134 (-1, 18.5) -> (-1, 26.5)
  line L135 (-1, 26.5) -> (1, 26.5)
  line L136 (1, 26.5) -> (1, 18.5)
  line L137 (22.0267, 14.7673) -> (15.5546, 10.065)
  line L138 (15.5546, 10.065) -> (14.379, 11.683)
  line L139 (14.379, 11.683) -> (20.8512, 16.3853)
  line L140 (20.8512, 16.3853) -> (22.0267, 14.7673)
  line L141 (18.0312, -19.4454) -> (12.3744, -13.7886)
  line L142 (12.3744, -13.7886) -> (13.7886, -12.3744)
  line L143 (13.7886, -12.3744) -> (19.4454, -18.0312)
  line L144 (19.4454, -18.0312) -> (18.0312, -19.4454)
  line L145 (26.3302, 3.1578) -> (18.4287, 1.9063)
  line L146 (18.4287, 1.9063) -> (18.1158, 3.8817)
  line L147 (18.1158, 3.8817) -> (26.0173, 5.1332)
  line L148 (26.0173, 5.1332) -> (26.3302, 3.1578)
  line L149 (24.0657, 11.1397) -> (16.9376, 7.5078)
  line L150 (16.9376, 7.5078) -> (16.0296, 9.2898)
  line L151 (16.0296, 9.2898) -> (23.1577, 12.9218)
  line L152 (23.1577, 12.9218) -> (24.0657, 11.1397)
  line L153 (-16.3853, -20.8512) -> (-11.683, -14.379)
  line L154 (-11.683, -14.379) -> (-10.065, -15.5546)
  line L155 (-10.065, -15.5546) -> (-14.7673, -22.0267)
  line L156 (-14.7673, -22.0267) -> (-16.3853, -20.8512)
  line L157 (-23.1577, 12.9218) -> (-16.0296, 9.2898)
  line L158 (-16.0296, 9.2898) -> (-16.9376, 7.5078)
  line L159 (-16.9376, 7.5078) -> (-24.0657, 11.1397)
  line L160 (-24.0657, 11.1397) -> (-23.1577, 12.9218)
  circle A1 centre (0, 0) radius 28
  circle A2 centre (0, 0) radius 2.65
  circle A3 centre (0, 0) radius 6
  dimension "d11" = 12
  dimension "d14" = 5.3
  constraint concentric A0 A2
  constraint coincident A0.centre A1.centre
  measures "d11" diameter of A3
  measures "d14" diameter of A2
extrude "Extruir2" add sketch "Boceto2" along normal blind 6 contours A3
fillet "Empalme1" radius 1.5 1 edges at (4, 2.1697, 5.594)

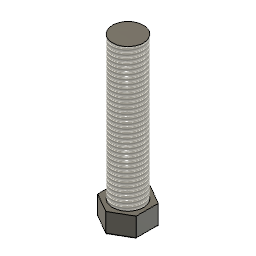
design "tornillo_contrapeso"
Autodesk Fusion 360 part; units mm, degrees
sketch "Boceto1" plane through (0, 0, 0) normal (0, 1, 0) x (1, 0, 0)
  circle A0 centre (0, 0) radius 7.8 construction
  line L0 (0, 7.8) -> (-6.755, 3.9)
  line L1 (-6.755, 3.9) -> (-6.755, -3.9)
  line L2 (-6.755, -3.9) -> (0, -7.8)
  line L3 (0, -7.8) -> (6.755, -3.9)
  line L4 (6.755, -3.9) -> (6.755, 3.9)
  line L5 (6.755, 3.9) -> (0, 7.8)
  dimension "d1" = 15.6
  constraint coincident A0.centre origin
  constraint coincident A0 L0.start
  measures "d1" diameter of A0
extrude "Extruir1" add sketch "Boceto1" along normal blind 7.1
sketch "Boceto2" plane through (0, 7.1, 0) normal (0, 1, 0) x (-1, 0, 0)
  line L0 (-6.755, -3.9) -> (0, -7.8)
  line L1 (0, -7.8) -> (6.755, -3.9)
  line L2 (6.755, -3.9) -> (6.755, 3.9)
  line L3 (6.755, 3.9) -> (0, 7.8)
  line L4 (0, 7.8) -> (-6.755, 3.9)
  line L5 (-6.755, 3.9) -> (-6.755, -3.9)
  circle A0 centre (0, 0) radius 5.5
  dimension "d4" = 11
  constraint coincident A0.centre origin
  measures "d4" diameter of A0
extrude "Extruir2" add sketch "Boceto2" along normal blind 50 contours A0
thread "Rosca1" "ISO Metric profile 11.0 M11x1.5 M11x1.5 6g" major diameter 10.85 minor diameter 9.1409 pitch 1.5 angle 60 resizes the face on face at (-5.4727, 23.7667, -0.5476)
fillet "Empalme1" radius 0.5 6 edges at (-3.3775, 0, -5.85) (3.3775, 0, -5.85) (6.755, 0, 0) (3.3775, 0, 5.85) (-3.3775, 0, 5.85) (-6.755, 0, 0)

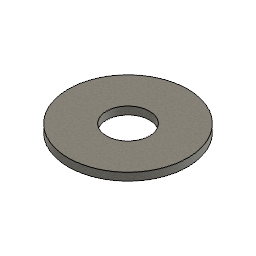
design "arandelas_contrapeso"
Autodesk Fusion 360 part; units mm, degrees
sketch "Boceto1" plane through (0, 0, 0) normal (0, 1, 0) x (1, 0, 0)
  circle A0 centre (0, 0) radius 15.35
  circle A1 centre (0, 0) radius 5.5
  dimension "d1" = 30.7
  dimension "d2" = 11
  constraint coincident A0.centre A1.centre
  constraint concentric A0 A1
  measures "d1" diameter of A0
  measures "d2" diameter of A1
extrude "Extruir1" add sketch "Boceto1" along normal blind 2

design "entrelape_bases_carro"
Autodesk Fusion 360 part; units mm, degrees
sketch "Boceto1" plane through (0, 0, 0) normal (0, 1, 0) x (1, 0, 0)
  line L0 (-30.15, 0) -> (0, 0)
  line L1 (0, 0) -> (0, 10)
  line L2 (0, 10) -> (-14.95, 10)
  line L3 (-30.15, 10) -> (-30.15, 0)
  line L4 (-14.95, 10) -> (-14.95, 2.5)
  line L5 (-14.95, 2.5) -> (-25.15, 2.5)
  line L6 (-25.15, 2.5) -> (-25.15, 10)
  line L7 (-25.15, 10) -> (-30.15, 10)
  line L8 (30.15, 10) -> (30.15, 0)
  line L9 (25.15, 10) -> (30.15, 10)
  line L10 (25.15, 2.5) -> (25.15, 10)
  line L11 (14.95, 2.5) -> (25.15, 2.5)
  line L12 (30.15, 0) -> (0, 0)
  line L13 (14.95, 10) -> (14.95, 2.5)
  line L14 (0, 10) -> (14.95, 10)
  dimension "d1" = 14.95
  dimension "d3" = 7.5
  dimension "d4" = 10
  dimension "d5" = 10.2
  dimension "d6" = 7.5
  dimension "d7" = 5
  dimension "d8" = 30.15
  dimension "d9" = 10
  constraint coincident L0.end L1.start
  constraint horizontal L0
  constraint perpendicular L0 L1
  constraint perpendicular L1 L2
  constraint perpendicular L2 L4
  constraint perpendicular L3 L5
  constraint perpendicular L5 L6
  constraint perpendicular L3 L7
  constraint symmetric L0.start L1 L8.end
  constraint symmetric L0.end L1 L12.end
  constraint symmetric L2.start L1 L14.start
  constraint symmetric L1 L2.end L13.start
  constraint symmetric L1 L4.end L11.start
  constraint symmetric L1 L5.end L10.start
  constraint symmetric L1 L6.end L9.start
  constraint symmetric L1 L3.start L8.start
  measures "d1" distance of L1.end L2.end
  measures "d3" distance of L2.end L4.end
  measures "d4" distance of L0.end L1.end
  measures "d5" distance of L4.end L5.end
  measures "d6" distance of L5.end L6.end
  measures "d7" distance of L6.end L3.start
  measures "d8" distance of L0.start L0.end
  measures "d9" distance of L0.start L3.start
extrude "Extruir1" add sketch "Boceto1" along normal blind 10
equation "d1 = ( 29.9 / 2 ) * 1 mm"

design "tapa_Encoder_HC020K"
Autodesk Fusion 360 part; units mm, degrees
sketch "Boceto1" plane through (0, 0, 0) normal (0, 1, 0) x (1, 0, 0)
  line L0 (9.9, 10.9) -> (-9.9, 10.9)
  line L1 (-9.9, -10.9) -> (9.9, -10.9)
  line L2 (9.9, 10.9) -> (-9.9, -10.9) construction
  line L3 (-9.9, 10.9) -> (9.9, -10.9) construction
  circle A0 centre (9.9, 7.4) radius 2
  line L4 (0, -2.845) -> (0, 2.6261) construction
  line L5 (-1.6752, 0) -> (2.3909, 0) construction
  circle A1 centre (-9.9, 7.4) radius 2
  arc A2 (-9.9, 10.9) -> (-11.9, 4.5277) centre (-9.9, 7.4) ccw
  arc A3 (11.9, 4.5277) -> (9.9, 10.9) centre (9.9, 7.4) ccw
  line L6 (-9.9, -10.9) -> (-11.9, -10.9)
  line L7 (-11.9, -10.9) -> (-11.9, 4.5277)
  line L8 (9.9, -10.9) -> (11.9, -10.9)
  line L9 (11.9, -10.9) -> (11.9, 4.5277)
  dimension "d1" = 19.8
  dimension "d2" = 21.8
  dimension "d3" = 7
  dimension "d4" = 3.5
  dimension "d5" = 4
  dimension "d6" = 19.8
  dimension "d32" = 2
  dimension "d33" = 2
  constraint horizontal L0
  constraint parallel L0 L1
  constraint coincident L2 origin
  constraint coincident L3 origin
  constraint concentric A0 A3
  constraint vertical L4
  constraint perpendicular L4 L5
  constraint symmetric L4 A2 A3
  constraint symmetric A0 L4 A1
  constraint perpendicular L6 L7
  constraint perpendicular L8 L9
  measures "d1" distance of L1.start L1.end
  measures "d2" distance of L0.end L1.start
  measures "d3" diameter of A3
  measures "d4" distance of L0.start A0.centre
  measures "d5" diameter of A0
  measures "d6" distance of A0.centre A1.centre
  measures "d32" distance of L1.start L6.end
  measures "d33" distance of L1.end L8.end
extrude "Extruir1" add sketch "Boceto1" along normal blind 1.5
sketch "Boceto2" plane through (0, 1.5, 0) normal (0, 1, 0) x (-1, 0, 0)
  circle A0 centre (9.9, -7.4) radius 2
  circle A1 centre (-9.9, -7.4) radius 2
  arc A2 (-11.9, -4.5277) -> (-9.9, -10.9) centre (-9.9, -7.4) ccw
  line L0 (-9.9, -10.9) -> (9.9, -10.9)
  arc A3 (9.9, -10.9) -> (11.9, -4.5277) centre (9.9, -7.4) ccw
  line L1 (11.9, 10.9) -> (-11.9, 10.9)
  circle A4 centre (9.9, -7.4) radius 2
  circle A5 centre (-9.9, -7.4) radius 2
  line L2 (9.9, -10.4) -> (-9.9, -10.4)
  line L3 (9.9, -4.4) -> (-9.9, -4.4)
  arc A6 (9.9, -10.4) -> (9.9, -4.4) centre (9.9, -7.4) ccw
  arc A7 (-9.9, -4.4) -> (-9.9, -10.4) centre (-9.9, -7.4) ccw
  line L4 (-11.9, 10.9) -> (-11.9, -4.5277)
  line L5 (11.9, -4.5277) -> (11.9, 10.9)
  dimension "d10" = 6
  dimension "d11" = 6
  constraint concentric A0 A4
  constraint concentric A4 A6
  constraint concentric A1 A5
  constraint concentric A5 A7
  constraint tangent L2 A7
  constraint horizontal L2
  constraint tangent L3 A7
  constraint parallel L2 L3
  measures "d10" diameter of A6
  measures "d11" diameter of A7
extrude "Extruir2" add sketch "Boceto2" along normal blind 7 contours A2 L0 A3 L1 L4 L5 | L2 L3 A6 A7
sketch "Boceto5" plane through (0, 0, 0) normal (0, -1, 0) x (1, 0, 0)
  line L0 (11.9, 10.9) -> (-11.9, 10.9)
  arc A0 (-11.9, -4.5277) -> (-9.9, -10.9) centre (-9.9, -7.4) ccw
  line L1 (-9.9, -10.9) -> (9.9, -10.9)
  arc A1 (9.9, -10.9) -> (11.9, -4.5277) centre (9.9, -7.4) ccw
  circle A2 centre (9.9, -7.4) radius 2
  circle A3 centre (-9.9, -7.4) radius 2
  circle A4 centre (7.4, 0.6) radius 2
  line L2 (0, 1.3993) -> (0, -2.7753) construction
  circle A5 centre (-7.4, 0.6) radius 2
  line L3 (-11.9, 10.9) -> (-11.9, -4.5277)
  line L4 (11.9, -4.5277) -> (11.9, 10.9)
  dimension "d24" = 4
  dimension "d25" = 8
  dimension "d26" = 2.5
  constraint vertical L2
  constraint symmetric A4 L2 A5
  measures "d24" diameter of A4
  measures "d25" vertical distance of A1.centre A4.centre
  measures "d26" horizontal distance of A1.centre A4.centre
extrude "Extruir5" cut sketch "Boceto5" against normal blind 9 contours A4 | A5
sketch "Boceto6" plane through (0, 8.5, 0) normal (0, 1, 0) x (-1, 0, 0)
  circle A0 centre (-9.9, -7.4) radius 2
  circle A1 centre (9.9, -7.4) radius 2
  arc A2 (-11.9, -4.5277) -> (-9.9, -10.9) centre (-9.9, -7.4) ccw
  line L0 (-9.9, -10.9) -> (9.9, -10.9)
  arc A3 (9.9, -10.9) -> (11.9, -4.5277) centre (9.9, -7.4) ccw
  line L1 (11.9, 10.9) -> (-11.9, 10.9)
  circle A4 centre (9.9, -7.4) radius 3.5
  circle A5 centre (-9.9, -7.4) radius 3.5
  line L2 (-8.2008, 9) -> (-8.2008, -4.3401)
  line L3 (8.2008, 9) -> (-8.2008, -9) construction
  line L4 (-8.2008, 9) -> (8.2008, -9) construction
  line L5 (8.2008, -4.3401) -> (8.2008, 9)
  line L6 (5.7075, -9) -> (5.7075, -10.9)
  line L7 (-5.6319, -10.9) -> (-5.6319, -9)
  line L8 (-6.7871, -9) -> (-5.6319, -9)
  line L9 (5.7075, -9) -> (6.7871, -9)
  line L10 (-8.2008, 9) -> (-8.2008, 10.9)
  line L11 (-8.2008, 10.9) -> (5.7075, 10.9)
  line L12 (8.2008, 9) -> (8.2008, 10.9)
  line L13 (5.7075, 10.9) -> (8.2008, 10.9)
  circle A6 centre (-7.4, 0.6) radius 2
  circle A7 centre (7.4, 0.6) radius 2
  line L14 (11.9, -4.5277) -> (11.9, 10.9)
  line L15 (-11.9, 10.9) -> (-11.9, -4.5277)
  dimension "d29" = 18
  constraint concentric A1 A4
  constraint coincident L0.end A4
  constraint concentric A0 A5
  constraint coincident A2.end A5
  constraint coincident L3 origin
  constraint coincident L4 origin
  constraint coincident A4 L5.start
  constraint coincident A4 L9.end
  constraint coincident A5 L8.start
  constraint coincident A5 L2.end
  constraint coincident L0 L6.end
  constraint perpendicular L0 L6
  constraint coincident L0 L7.start
  constraint perpendicular L7 L8
  constraint collinear L8 L9
  constraint coincident L1 L11.end
  constraint coincident L1 L10.end
  constraint perpendicular L1 L10
  constraint coincident L1 L12.end
  constraint perpendicular L1 L12
  measures "d29" distance of L2.start L3.end
extrude "Extruir6" cut sketch "Boceto6" against normal blind 5 contours L0 L1 A4 A5 L2 L5 L6 L7 L8 L9 L10 L11 L12 L13 A6 A7
equation "d3 = ( 3.5 * 2 ) * 1 mm"

design "Encoder_HC020K"
Autodesk Fusion 360 part; units mm, degrees
sketch "Boceto1" plane through (0, 0, 0) normal (0, 1, 0) x (1, 0, 0)
  line L0 (9.9, 10.9) -> (-9.9, 10.9)
  line L1 (-9.9, -10.9) -> (9.9, -10.9)
  line L2 (9.9, -10.9) -> (9.9, 3.9)
  line L3 (9.9, 10.9) -> (-9.9, -10.9) construction
  line L4 (-9.9, 10.9) -> (9.9, -10.9) construction
  circle A0 centre (9.9, 7.4) radius 2
  line L5 (0, -2.845) -> (0, 2.6261) construction
  line L6 (-1.6752, 0) -> (2.3909, 0) construction
  circle A1 centre (-9.9, 7.4) radius 2
  line L7 (-9.9, 3.9) -> (-9.9, -10.9)
  arc A2 (-9.9, 10.9) -> (-9.9, 3.9) centre (-9.9, 7.4) ccw
  arc A3 (9.9, 3.9) -> (9.9, 10.9) centre (9.9, 7.4) ccw
  dimension "d1" = 19.8
  dimension "d2" = 21.8
  dimension "d3" = 7
  dimension "d4" = 3.5
  dimension "d5" = 4
  dimension "d6" = 19.8
  dimension "d7" = 14.8
  constraint horizontal L0
  constraint parallel L0 L1
  constraint coincident L3 origin
  constraint coincident L4 origin
  constraint coincident L2 A0.centre
  constraint concentric A0 A3
  constraint vertical L5
  constraint perpendicular L5 L6
  constraint symmetric L5 A2 A3
  constraint symmetric A0 L5 A1
  measures "d1" distance of L1.start L1.end
  measures "d2" distance of L0.end L1.start
  measures "d3" diameter of A3
  measures "d4" distance of L0.start A0.centre
  measures "d5" diameter of A0
  measures "d6" distance of A0.centre A1.centre
  measures "d7" distance of L1.start L7.start
extrude "Extruir1" add sketch "Boceto1" along normal blind 1.5
sketch "Boceto2" plane through (0, 1.5, 0) normal (0, 1, 0) x (-1, 0, 0)
  circle A0 centre (9.9, -7.4) radius 2
  circle A1 centre (-9.9, -7.4) radius 2
  arc A2 (-9.9, -3.9) -> (-9.9, -10.9) centre (-9.9, -7.4) ccw
  line L0 (-9.9, -10.9) -> (9.9, -10.9)
  arc A3 (9.9, -10.9) -> (9.9, -3.9) centre (9.9, -7.4) ccw
  line L1 (9.9, -3.9) -> (9.9, 10.9)
  line L2 (9.9, 10.9) -> (-9.9, 10.9)
  line L3 (-9.9, 10.9) -> (-9.9, -3.9)
  circle A4 centre (9.9, -7.4) radius 2
  circle A5 centre (-9.9, -7.4) radius 2
  line L4 (9.9, -10.4) -> (-9.9, -10.4)
  line L5 (9.9, -4.4) -> (-9.9, -4.4)
  arc A6 (9.9, -10.4) -> (9.9, -4.4) centre (9.9, -7.4) ccw
  arc A7 (-9.9, -4.4) -> (-9.9, -10.4) centre (-9.9, -7.4) ccw
  dimension "d10" = 6
  dimension "d11" = 6
  constraint concentric A0 A4
  constraint concentric A4 A6
  constraint concentric A1 A5
  constraint concentric A5 A7
  constraint tangent L4 A7
  constraint horizontal L4
  constraint tangent L5 A7
  constraint parallel L4 L5
  measures "d10" diameter of A6
  measures "d11" diameter of A7
extrude "Extruir2" add sketch "Boceto2" along normal blind 2.8 contours L4 L5 A6 A7
sketch "Boceto3" plane through (0, 4.3, 0) normal (0, 1, 0) x (-1, 0, 0)
  circle A0 centre (-9.9, -7.4) radius 2
  circle A1 centre (9.9, -7.4) radius 2
  arc A2 (9.9, -10.4) -> (9.9, -4.4) centre (9.9, -7.4) ccw
  line L0 (9.9, -4.4) -> (-9.9, -4.4)
  arc A3 (-9.9, -4.4) -> (-9.9, -10.4) centre (-9.9, -7.4) ccw
  line L1 (-9.9, -10.4) -> (9.9, -10.4)
  line L2 (0, 0) -> (0, -11.5742) construction
  line L3 (9.9, -7.4) -> (-9.9, -7.4) construction
  line L4 (7, -4.4) -> (-7, -4.4)
  line L5 (-7, -4.4) -> (-7, -10.4)
  line L6 (-7, -10.4) -> (7, -10.4)
  line L7 (7, -10.4) -> (7, -4.4)
  line L8 (7, -4.4) -> (-7, -10.4) construction
  line L9 (-7, -4.4) -> (7, -10.4) construction
  line L10 (-7, -10.4) -> (-3, -10.4)
  line L11 (-3, -10.4) -> (-3, -4.4)
  line L12 (-3, -4.4) -> (-7, -4.4)
  line L13 (-7, -4.4) -> (-7, -10.4)
  line L14 (7, -10.4) -> (3, -10.4)
  line L15 (3, -10.4) -> (3, -4.4)
  line L16 (3, -4.4) -> (7, -4.4)
  line L17 (7, -4.4) -> (7, -10.4)
  point P0 (0, -7.4)
  dimension "d14" = 14
  dimension "d15" = 6
  dimension "d16" = 4
  dimension "d17" = 4
  constraint coincident L2.start origin
  constraint perpendicular L1 L2
  constraint coincident A1.centre A2.centre
  constraint coincident A0.centre A3.centre
  constraint horizontal L4
  constraint perpendicular L4 L5
  constraint parallel L4 L6
  constraint parallel L5 L7
  constraint coincident L8 P0
  constraint coincident L9 P0
  constraint midpoint L3 P0
  constraint horizontal L10
  constraint vertical L11
  constraint horizontal L12
  constraint vertical L13
  constraint horizontal L14
  constraint vertical L15
  constraint horizontal L16
  constraint vertical L17
  measures "d14" distance of L5.end L6.end
  measures "d15" distance of L4.end L5.end
  measures "d16" distance of L5.end L10.end
  measures "d17" distance of L6.end L14.end
extrude "Extruir3" add sketch "Boceto3" along normal blind 8.3 contours L0 L1 L4 L6 L7 L14 L15 L16 L17 | L0 L1 L4 L5 L6 L10 L11 L12 L13
sketch "Boceto4" plane through (0, 0, 0) normal (0, -1, 0) x (1, 0, 0)
  circle A0 centre (-9.9, -7.4) radius 2
  circle A1 centre (9.9, -7.4) radius 2
  arc A2 (9.9, -10.9) -> (9.9, -3.9) centre (9.9, -7.4) ccw
  line L0 (9.9, -3.9) -> (9.9, 10.9)
  line L1 (9.9, 10.9) -> (-9.9, 10.9)
  line L2 (-9.9, 10.9) -> (-9.9, -3.9)
  arc A3 (-9.9, -3.9) -> (-9.9, -10.9) centre (-9.9, -7.4) ccw
  line L3 (-9.9, -10.9) -> (9.9, -10.9)
  line L4 (-3, 10.9) -> (-3, 4.9)
  line L5 (-3, 4.9) -> (3, 4.9)
  line L6 (3, 4.9) -> (3, 10.9)
  line L7 (0, 10.9) -> (-3, 4.9) construction
  line L8 (0, 10.9) -> (3, 4.9) construction
  line L9 (-3, 10.9) -> (3, 10.9)
  dimension "d20" = 6
  constraint parallel L4 L6
  constraint midpoint L1 L7.start
  constraint coincident L1 L4.start
  constraint coincident L1 L6.end
  constraint perpendicular L6 L9
  measures "d20" distance of L4.end L5.end
extrude "Extruir4" add sketch "Boceto4" along normal blind 4 contours L1 L4 L5 L6 L9
sketch "Boceto5" plane through (0, 0, 0) normal (0, -1, 0) x (1, 0, 0)
  line L0 (3, 10.9) -> (3, 4.9)
  line L1 (3, 4.9) -> (-3, 4.9)
  line L2 (-3, 4.9) -> (-3, 10.9)
  line L3 (-3, 10.9) -> (-9.9, 10.9)
  line L4 (-9.9, 10.9) -> (-9.9, -3.9)
  arc A0 (-9.9, -3.9) -> (-9.9, -10.9) centre (-9.9, -7.4) ccw
  line L5 (-9.9, -10.9) -> (9.9, -10.9)
  arc A1 (9.9, -10.9) -> (9.9, -3.9) centre (9.9, -7.4) ccw
  line L6 (9.9, -3.9) -> (9.9, 10.9)
  line L7 (9.9, 10.9) -> (3, 10.9)
  circle A2 centre (9.9, -7.4) radius 2
  circle A3 centre (-9.9, -7.4) radius 2
  circle A4 centre (7.4, 0.6) radius 2
  line L8 (0, 1.3993) -> (0, -2.7753) construction
  circle A5 centre (-7.4, 0.6) radius 2
  dimension "d24" = 4
  dimension "d25" = 8
  dimension "d26" = 2.5
  constraint vertical L8
  constraint symmetric A4 L8 A5
  measures "d24" diameter of A4
  measures "d25" vertical distance of A1.centre A4.centre
  measures "d26" horizontal distance of A1.centre A4.centre
extrude "Extruir5" cut sketch "Boceto5" against normal blind 2 contours A4 | A5
equation "d3 = ( 3.5 * 2 ) * 1 mm"

design "Codo_pendulo_2"
Autodesk Fusion 360 part; units mm, degrees
sketch "Boceto1" plane through (0, 0, 0) normal (1, 0, 0) x (0, 0, -1)
  circle A0 centre (0, 0) radius 6.5
  circle A1 centre (0, 0) radius 12.5
  dimension "d1" = 13
  dimension "d2" = 25
  constraint coincident A0.centre A1.centre
  measures "d1" diameter of A0
  measures "d2" diameter of A1
extrude "Extruir1" add sketch "Boceto1" along normal blind 70